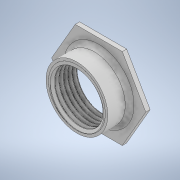
# Autodesk Inventor part: PIULITA_BUN
Saved by Autodesk Inventor 2020 (Build 240168000, 168)
## iProperties
Created: 2023-11-01
Part Number: PIULITA_BUN
Material: Generic
Document SubType Name: Modeling
Designer: user
Density: 1 g/cm^3
Appearance: Default
Author: user
Autodesk Inventor part; units mm, degrees
ref_plane "YZ Plane" through (0, 0, 0) normal (1, 0, 0) x (0, 1, 0)
ref_plane "XZ Plane" through (0, 0, 0) normal (0, 1, 0) x (-1, 0, 0)
ref_plane "XY Plane" through (0, 0, 0) normal (0, 0, 1) x (1, 0, 0)
sketch "Sketch1" plane through (0, 0, 0) normal (0, 0, 1) x (1, 0, 0)
  circle A0 centre (0, 0) radius 13
  circle A1 centre (0, 0) radius 14.15
  dimension "d0" = 26
  dimension "d1" = 28.3
  constraints: 2 centre point, 2 coincident
  measures "d0" diameter of A0
  measures "d1" diameter of A1
extrude "Extrusion1" add sketch "Sketch1" along normal blind 12
sketch "Sketch13" plane through (0, 0, 0) normal (0, 0, -1) x (-1, 0, 0)
  circle A0 centre (0, 0) radius 14.15 projected
  circle A1 centre (0, 0) radius 18.65
  line L0 (10.7803, -18.65) -> (-10.7612, -18.661)
  line L1 (-10.7612, -18.661) -> (-21.5415, -0.011)
  line L2 (-21.5415, -0.011) -> (-10.7803, 18.65)
  line L3 (-10.7803, 18.65) -> (10.7612, 18.661)
  line L4 (10.7612, 18.661) -> (21.5415, 0.011)
  line L5 (21.5415, 0.011) -> (10.7803, -18.65)
  dimension "d104" = 4.5
  constraints: 12 end point, 2 coincident, 1 centre point, 13 other
  measures "d104" radial gap between concentric circles of A0 A1
extrude "Extrusion2" add sketch "Sketch13" against normal blind 2 contours A1 | L0 L1 L2 L3 L4 L5
fillet "Fillet1" radius 2 1 edges at (-14.15, 0, 2)
thread "Thread6" size "M27x2" class "6H" standard "ANSI Metric M Profile" full length
sketch "Sketch15" plane through (0, 0, 12) normal (-1, 0, 0) x (0, 1, 0)
  line L0 (13, 0) -> (13, 12)
  line L1 (13, 12) -> (11.5171, 12)
  line L2 (11.5171, 12) -> (11.5171, 0)
  line L3 (11.5171, 0) -> (13, 0)
  line L4 (0, -5.0171) -> (0, 14.8362) projected
  constraints: 8 end point
revolve "Revolution6" add sketch "Sketch15" angle 360 about axis through (0, 0, 12) along (0, 0, -1) separate body
sketch "Sketch14" plane through (0, 13, 12) normal (1, 0, 0) x (0, 0, -1)
  line L0 (-1.1668, -0.1013) -> (-1.0001, -0.1013) construction
  line L1 (0.1666, -1.382) -> (-0.0001, -1.7021) construction
  line L2 (-2.0001, -1.7021) -> (-2.1668, -1.382) construction
  line L3 (-0.8334, -0.1013) -> (-1.0001, 0.2189) construction
  line L4 (-1.0001, 0.2189) -> (-1.1668, -0.1013) construction
  line L5 (-2.0001, -1.7021) -> (-1.8334, -1.382) construction
  line L6 (-0.8334, -0.1013) -> (-0.1668, -1.382)
  line L7 (-2.1668, -1.382) -> (-1.8334, -1.382) construction
  arc A0 (-2.1668, -1.382) -> (-2.0001, -1.4831) centre (-2.0001, -1.2952) ccw construction
  line L8 (0.1666, -1.382) -> (-0.1668, -1.382) construction
  line L9 (-2.0001, -1.7021) -> (-2.0001, -1.382) construction
  line L10 (-0.0001, -1.7021) -> (-0.0001, -1.382) construction
  line L11 (-1.0001, 0.2189) -> (-1.0001, -0.0002) construction
  line L12 (-2.0001, -1.4831) -> (-0.0001, -1.4831)
  arc A1 (-2.0001, -1.4831) -> (-1.8334, -1.382) centre (-2.0001, -1.2952) ccw
  line L13 (-0.1668, -1.382) -> (-0.0001, -1.7021) construction
  line L14 (-1.8334, -1.382) -> (-1.1668, -0.1013)
  line L15 (-0.0001, -0.0002) -> (-0.0001, 0.0177)
  line L16 (-0.0001, 0.0177) -> (-0.0001, -0.0002)
  line L17 (-0.0001, -0.0002) -> (0.0334, -0.0002)
  arc A2 (-0.1668, -1.382) -> (-0.0001, -1.4831) centre (-0.0001, -1.2952) ccw
  arc A3 (-0.0001, -1.4831) -> (0.1666, -1.382) centre (-0.0001, -1.2952) ccw construction
  arc A4 (-1.0001, -0.0002) -> (-1.1668, -0.1013) centre (-1.0001, -0.1881) ccw
  arc A5 (-0.8334, -0.1013) -> (-1.0001, -0.0002) centre (-1.0001, -0.1881) ccw
  line L18 (-1.0001, -0.0002) -> (-1.0001, -0.1013) construction
  line L19 (-1.0001, -0.1013) -> (-0.8334, -0.1013) construction
  dimension "d110" = 55
  dimension "d111" = 0.3202
  dimension "d112" = 0.3202
  dimension "Sketch14_ThreadOffset" = 0
  dimension "Sketch14_MajorRadius" = 1.4829
  dimension "d115" = 2
  dimension "Sketch14_MinorRadius" = 0
  constraints: 40 end point, 12 point on circle, 10 parallel, 8 tangent, 6 centre point, 6 collinear, 2 midpoint, 2 point on line, 1 horizontal, 1 perpendicular, 3 other
  measures "d110" angle of L6 L14
  measures "d111" distance of L3.end L0.end
  measures "d112" distance of L1.end L10.end
  measures "Sketch14_ThreadOffset" distance between parallel lines of L15 L10
  measures "Sketch14_MajorRadius" distance from line of L12 L15.start
  measures "d115" distance from line of L1.end L9
  measures "Sketch14_MinorRadius" distance edge to line of A5 L17
coil "Coil6" sketch "Sketch14" operation cut axis through (0, 0, 12) along (0, 0, -1) pitch 2.002 turns 7.992008 hand right bodies 2
equation "\"d110\" = d117"
equation "\"d111\" = 0.160083 * Sketch14_Pitch"
equation "\"d112\" = 0.160083 * Sketch14_Pitch"
equation "\"d115\" = Sketch14_Pitch"
equation "\"d13\" = 55deg"
equation "\"Sketch2_Pitch\" = 2"
equation "\"d33\" = 55deg"
equation "\"Sketch5_Pitch\" = 1.5"
equation "\"d53\" = 55deg"
equation "\"Sketch7_Pitch\" = 2"
equation "\"d73\" = 55deg"
equation "\"Sketch9_Pitch\" = 2"
equation "\"d93\" = 55deg"
equation "\"Sketch11_Pitch\" = 2"
equation "\"d117\" = 55deg"
equation "\"Sketch14_Pitch\" = 2"
body "Solid1"
body "Solid7"
